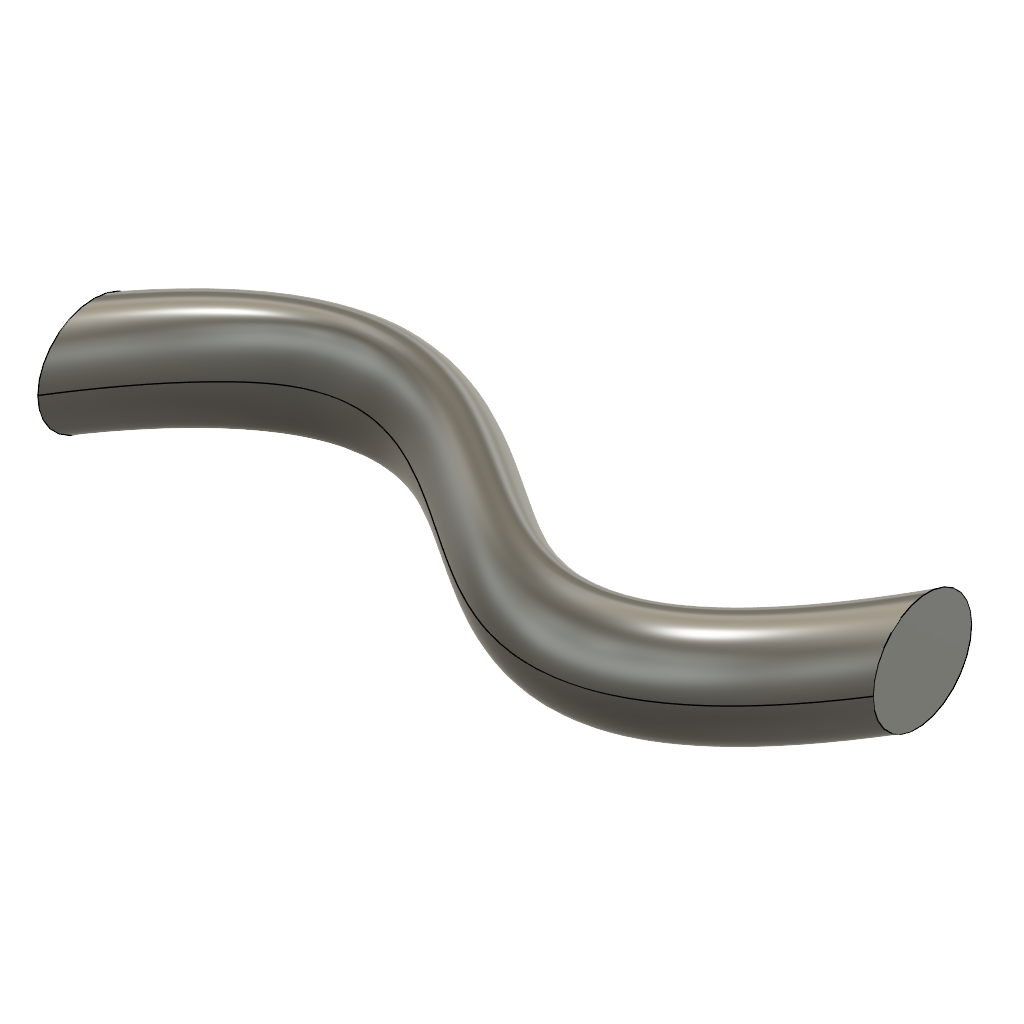
sweep_spline_path (Autodesk Fusion 360 design; units mm, degrees)
part number: 2026-11-13-14-38-49-231
Autodesk Fusion 360 part; units mm, degrees
sketch "Sketch1" plane through (0, 0, 0) normal (1, 0, 0) x (0, 0, -1)
  circle A0 centre (0, 0) radius 2.5
sketch "Sketch2" plane through (0, 0, 0) normal (0, 1, 0) x (1, 0, 0)
  spline S0 degree 5 poles (0, 0) (0.4027, 0.5468) (1.2087, 1.5703) (2.4195, 2.8953) (4.0378, 4.2382) (6.0669, 5.2041) (8.1017, 5.4702) (10.1409, 5.0893) (12.1822, 4.1777) (14.2216, 2.938) (16.2545, 1.6206) (18.276, 0.4892) (20.2817, -0.2121) (22.2682, -0.2962) (24.234, 0.337) (26.1786, 1.7309) (27.7175, 3.4601) (28.8623, 5.0983) (29.6215, 6.341) (30, 7) knots 0 0 0 0 0 0 0.066667 0.133333 0.2 0.266667 0.333333 0.4 0.466667 0.533333 0.6 0.666667 0.733333 0.8 0.866667 0.933333 1 1 1 1 1 1
  point P0 (10, 5)
  point P1 (20, 0)
sweep "Sweep1" add profiles "Sketch1" path "Sketch2" along S0 section 1
